Autodesk Fusion 360 part; units mm, degrees
(part 2 of 6)
sketch "Skizze3" plane through (0, 0, 0) normal (0, 1, 0) x (1, 0, 0)
  spline S0 degree 5 poles (100, -0.079) (99.9701, -0.0818) (99.9078, -0.0877) (99.8067, -0.0976) (99.657, -0.1128) (99.4452, -0.1351) (99.2102, -0.1605) (98.9548, -0.1887) (98.6833, -0.2193) (98.4004, -0.2518) (98.111, -0.2858) (97.8191, -0.3207) (97.527, -0.3562) (97.2355, -0.3922) (96.9443, -0.4285) (96.6525, -0.4653) (96.359, -0.5023) (96.0633, -0.5398) (95.7651, -0.5776) (95.4651, -0.6157) (95.1639, -0.6542) (94.8622, -0.6928) (94.5608, -0.7315) (94.2597, -0.7704) (93.9591, -0.8094) (93.6589, -0.8484) (93.3586, -0.8874) (93.058, -0.9265) (92.7571, -0.9656) (92.4557, -1.0047) (92.1541, -1.0439) (91.8523, -1.0832) (91.5504, -1.1226) (91.2487, -1.162) (90.9472, -1.2014) (90.6458, -1.2409) (90.3445, -1.2803) (90.0433, -1.3196) (89.742, -1.3589) (89.4406, -1.3981) (89.1392, -1.4371) (88.8377, -1.4761) (88.5362, -1.5151) (88.2347, -1.554) (87.9332, -1.5928) (87.6317, -1.6317) (87.3304, -1.6706) (87.029, -1.7094) (86.7278, -1.7483) (86.4266, -1.7871) (86.1253, -1.8258) (85.8242, -1.8645) (85.523, -1.903) (85.2218, -1.9413) (84.9206, -1.9795) (84.6194, -2.0175) (84.3181, -2.0554) (84.0169, -2.0932) (83.7156, -2.1308) (83.4143, -2.1685) (83.1131, -2.2061) (82.8119, -2.2437) (82.5107, -2.2812) (82.2095, -2.3187) (81.9084, -2.356) (81.6073, -2.3931) (81.3063, -2.4301) (81.0053, -2.467) (80.7043, -2.5037) (80.4032, -2.5403) (80.1022, -2.5768) (79.8011, -2.6132) (79.5, -2.6496) (79.1988, -2.6858) (78.8976, -2.722) (78.5964, -2.758) (78.2953, -2.7938) (77.9941, -2.8294) (77.693, -2.8648) (77.3919, -2.9) (77.0908, -2.9351) (76.7897, -2.97) (76.4886, -3.0048) (76.1875, -3.0395) (75.8863, -3.0741) (75.5852, -3.1086) (75.284, -3.1429) (74.9827, -3.1772) (74.6815, -3.2112) (74.3803, -3.2452) (74.0791, -3.2789) (73.7779, -3.3126) (73.4767, -3.3461) (73.1757, -3.3794) (72.8746, -3.4126) (72.5736, -3.4455) (72.2726, -3.4783) (71.9715, -3.5109) (71.6704, -3.5433) (71.3692, -3.5754) (71.068, -3.6073) (70.7668, -3.639) (70.4655, -3.6706) (70.1643, -3.702) (69.863, -3.7332) (69.5618, -3.7642) (69.2605, -3.7951) (68.9593, -3.8259) (68.658, -3.8565) (68.3567, -3.887) (68.0554, -3.9173) (67.754, -3.9474) (67.4527, -3.9773) (67.1514, -4.007) (66.8502, -4.0365) (66.5489, -4.0657) (66.2477, -4.0948) (65.9464, -4.1237) (65.6452, -4.1523) (65.3439, -4.1809) (65.0425, -4.2092) (64.7412, -4.2374) (64.4397, -4.2653) (64.1383, -4.293) (63.8369, -4.3203) (63.5354, -4.3474) (63.234, -4.3742) (62.9325, -4.4008) (62.6311, -4.4272) (62.3296, -4.4535) (62.0281, -4.4797) (61.7266, -4.5058) (61.425, -4.5319) (61.1234, -4.5578) (60.8218, -4.5835) (60.5202, -4.6089) (60.2185, -4.634) (59.9169, -4.6587) (59.6152, -4.6831) (59.3136, -4.7073) (59.0119, -4.7312) (58.7103, -4.755) (58.4086, -4.7786) (58.1069, -4.8022) (57.8052, -4.8256) (57.5035, -4.8489) (57.2018, -4.872) (56.9002, -4.8949) (56.5985, -4.9176) (56.2968, -4.9401) (55.995, -4.9622) (55.6933, -4.9841) (55.3915, -5.0057) (55.0897, -5.0271) (54.7878, -5.0482) (54.4859, -5.0692) (54.184, -5.0899) (53.8821, -5.1106) (53.5802, -5.1311) (53.2783, -5.1515) (52.9765, -5.1717) (52.6746, -5.1917) (52.3727, -5.2115) (52.0708, -5.2309) (51.7688, -5.25) (51.4669, -5.2688) (51.165, -5.2873) (50.863, -5.3055) (50.561, -5.3236) (50.2591, -5.3415) (49.9571, -5.3592) (49.6551, -5.3768) (49.3531, -5.3942) (49.0511, -5.4114) (48.7492, -5.4283) (48.4473, -5.4451) (48.1454, -5.4617) (47.8435, -5.478) (47.5416, -5.4941) (47.2397, -5.51) (46.9377, -5.5257) (46.6358, -5.5411) (46.3339, -5.5563) (46.0319, -5.5712) (45.7299, -5.5858) (45.428, -5.6001) (45.126, -5.6141) (44.824, -5.6279) (44.522, -5.6414) (44.22, -5.6547) (43.918, -5.6677) (43.6161, -5.6805) (43.3142, -5.6931) (43.0123, -5.7055) (42.7104, -5.7176) (42.4085, -5.7295) (42.1066, -5.7411) (41.8047, -5.7524) (41.5029, -5.7635) (41.2011, -5.7742) (40.8992, -5.7846) (40.5974, -5.7946) (40.2955, -5.8044) (39.9937, -5.8138) (39.6919, -5.823) (39.3902, -5.8319) (39.0885, -5.8405) (38.7868, -5.8489) (38.4851, -5.8571) (38.1835, -5.865) (37.8819, -5.8725) (37.5803, -5.8797) (37.2788, -5.8866) (36.9772, -5.8931) (36.6757, -5.8992) (36.3741, -5.905) (36.0726, -5.9104) (35.7711, -5.9156) (35.4695, -5.9204) (35.168, -5.925) (34.8666, -5.9293) (34.5651, -5.9333) (34.2637, -5.937) (33.9623, -5.9404) (33.661, -5.9434) (33.3597, -5.946) (33.0584, -5.9483) (32.7572, -5.9501) (32.456, -5.9515) (32.1548, -5.9524) (31.8537, -5.9529) (31.5526, -5.9531) (31.2515, -5.9528) (30.9504, -5.9522) (30.6494, -5.9512) (30.3485, -5.9499) (30.0475, -5.9482) (29.7466, -5.9461) (29.4458, -5.9436) (29.145, -5.9407) (28.8442, -5.9373) (28.5435, -5.9336) (28.2429, -5.9294) (27.9424, -5.9248) (27.6419, -5.9197) (27.3415, -5.9143) (27.0412, -5.9084) (26.741, -5.902) (26.4408, -5.8951) (26.1407, -5.8877) (25.8407, -5.8797) (25.5407, -5.8711) (25.2407, -5.8621) (24.9408, -5.8525) (24.641, -5.8425) (24.3412, -5.832) (24.0416, -5.8211) (23.742, -5.8097) (23.4425, -5.7978) (23.1431, -5.7854) (22.8438, -5.7724) (22.5447, -5.7588) (22.2456, -5.7445) (21.9467, -5.7296) (21.648, -5.7141) (21.3493, -5.6979) (21.0508, -5.6811) (20.7525, -5.6637) (20.4543, -5.6456) (20.1562, -5.627) (19.8583, -5.6077) (19.5606, -5.5877) (19.263, -5.5672) (18.9656, -5.5459) (18.6684, -5.5239) (18.3713, -5.5011) (18.0744, -5.4776) (17.7777, -5.4533) (17.4812, -5.4281) (17.1849, -5.4022) (16.8888, -5.3754) (16.5929, -5.3479) (16.2973, -5.3196) (16.002, -5.2905) (15.707, -5.2606) (15.4122, -5.2298) (15.1177, -5.198) (14.8235, -5.1652) (14.5295, -5.1315) (14.2358, -5.0967) (13.9425, -5.0609) (13.6494, -5.0241) (13.3568, -4.9863) (13.0645, -4.9475) (12.7726, -4.9076) (12.4812, -4.8668) (12.1903, -4.8248) (11.8998, -4.7817) (11.6099, -4.7374) (11.3205, -4.6919) (11.0316, -4.6451) (10.7433, -4.597) (10.4555, -4.5475) (10.1683, -4.4967) (9.8818, -4.4445) (9.5959, -4.3909) (9.3107, -4.3358) (9.0263, -4.2794) (8.7426, -4.2214) (8.4599, -4.1619) (8.1781, -4.1008) (7.8973, -4.038) (7.6176, -3.9735) (7.3391, -3.9071) (7.0618, -3.839) (6.786, -3.7689) (6.5116, -3.6969) (6.2388, -3.623) (5.9678, -3.5472) (5.6986, -3.4695) (5.4315, -3.3897) (5.1666, -3.3078) (4.9042, -3.2237) (4.6446, -3.1373) (4.3879, -3.0486) (4.1346, -2.9576) (3.885, -2.8644) (3.6396, -2.769) (3.3988, -2.6717) (3.1631, -2.5726) (2.9332, -2.4717) (2.7096, -2.3694) (2.493, -2.2657) (2.2839, -2.161) (2.083, -2.0552) (1.8907, -1.9488) (1.7074, -1.8419) (1.5334, -1.735) (1.369, -1.6286) (1.2143, -1.5232) (1.0693, -1.4191) (0.934, -1.316) (0.8082, -1.2129) (0.6918, -1.1092) (0.5844, -1.0058) (0.4855, -0.9051) (0.3947, -0.8087) (0.3123, -0.7125) (0.2388, -0.6096) (0.1745, -0.5023) (0.1187, -0.4087) (0.0713, -0.3317) (0.0338, -0.2303) (0.0087, -0.0853) (-0.0021, -0.004) (-0.0007, -0.0204) (0.0044, 0.0795) (0.0265, 0.2057) (0.072, 0.289) (0.1329, 0.3635) (0.2038, 0.4498) (0.2851, 0.5349) (0.3772, 0.6098) (0.4783, 0.6797) (0.587, 0.7508) (0.7036, 0.8233) (0.829, 0.8947) (0.9638, 0.9637) (1.108, 1.031) (1.2616, 1.0977) (1.4247, 1.1643) (1.5975, 1.2308) (1.7805, 1.2969) (1.9736, 1.3623) (2.1766, 1.4267) (2.3892, 1.4899) (2.6108, 1.5518) (2.8408, 1.6123) (3.0785, 1.6712) (3.3234, 1.7284) (3.5747, 1.7837) (3.8317, 1.8372) (4.0938, 1.8889) (4.3604, 1.9386) (4.6308, 1.9864) (4.9046, 2.0324) (5.1812, 2.0766) (5.4603, 2.119) (5.7416, 2.1597) (6.0247, 2.1989) (6.3095, 2.2364) (6.5958, 2.2725) (6.8833, 2.3072) (7.1719, 2.3406) (7.4616, 2.3727) (7.7521, 2.4037) (8.0434, 2.4334) (8.3354, 2.462) (8.628, 2.4895) (8.9213, 2.5159) (9.2152, 2.5411) (9.5096, 2.5653) (9.8044, 2.5884) (10.0998, 2.6106) (10.3955, 2.6319) (10.6917, 2.6524) (10.9882, 2.6722) (11.285, 2.6913) (11.5821, 2.7097) (11.8795, 2.7274) (12.1771, 2.7445) (12.475, 2.7608) (12.7732, 2.7763) (13.0716, 2.7912) (13.3702, 2.8053) (13.669, 2.8188) (13.968, 2.8316) (14.2672, 2.8438) (14.5665, 2.8554) (14.866, 2.8665) (15.1656, 2.8771) (15.4653, 2.8873) (15.7652, 2.8971) (16.0651, 2.9065) (16.3652, 2.9154) (16.6655, 2.9239) (16.9658, 2.9318) (17.2663, 2.9393) (17.567, 2.9462) (17.8678, 2.9525) (18.1687, 2.9585) (18.4697, 2.964) (18.7707, 2.9692) (19.0719, 2.974) (19.3731, 2.9786) (19.6743, 2.9829) (19.9756, 2.9869) (20.277, 2.9905) (20.5784, 2.9937) (20.8799, 2.9966) (21.1814, 2.9991) (21.4831, 3.0012) (21.7849, 3.0031) (22.0867, 3.0047) (22.3886, 3.0061) (22.6906, 3.0073) (22.9927, 3.0082) (23.2948, 3.0088) (23.5969, 3.0091) (23.8989, 3.009) (24.201, 3.0086) (24.5031, 3.0078) (24.8052, 3.0068) (25.1074, 3.0055) (25.4096, 3.0041) (25.7119, 3.0026) (26.0143, 3.0009) (26.3167, 2.999) (26.6192, 2.9968) (26.9216, 2.9944) (27.2241, 2.9916) (27.5265, 2.9885) (27.829, 2.9851) (28.1314, 2.9815) (28.434, 2.9777) (28.7366, 2.9737) (29.0393, 2.9696) (29.342, 2.9655) (29.6448, 2.9611) (29.9476, 2.9566) (30.2504, 2.9518) (30.5532, 2.9468) (30.856, 2.9416) (31.1587, 2.9361) (31.4614, 2.9305) (31.7642, 2.9247) (32.067, 2.9188) (32.3699, 2.9129) (32.6728, 2.9068) (32.9758, 2.9006) (33.2788, 2.8942) (33.5817, 2.8876) (33.8847, 2.8808) (34.1876, 2.8737) (34.4905, 2.8664) (34.7934, 2.8589) (35.0963, 2.8513) (35.3993, 2.8435) (35.7023, 2.8356) (36.0054, 2.8276) (36.3085, 2.8195) (36.6117, 2.8114) (36.9148, 2.803) (37.218, 2.7946) (37.5211, 2.786) (37.8242, 2.7772) (38.1273, 2.7683) (38.4303, 2.7592) (38.7334, 2.75) (39.0364, 2.7406) (39.3394, 2.7312) (39.6425, 2.7216) (39.9456, 2.7119) (40.2488, 2.7021) (40.552, 2.6922) (40.8552, 2.6823) (41.1585, 2.6722) (41.4618, 2.662) (41.7651, 2.6518) (42.0683, 2.6413) (42.3716, 2.6308) (42.6748, 2.6201) (42.9781, 2.6092) (43.2813, 2.5981) (43.5845, 2.5869) (43.8878, 2.5756) (44.191, 2.5641) (44.4943, 2.5525) (44.7975, 2.5409) (45.1007, 2.5291) (45.4039, 2.5174) (45.7071, 2.5055) (46.0103, 2.4937) (46.3135, 2.4817) (46.6168, 2.4697) (46.92, 2.4576) (47.2234, 2.4453) (47.5268, 2.433) (47.8302, 2.4205) (48.1336, 2.4079) (48.4371, 2.3952) (48.7405, 2.3824) (49.0439, 2.3695) (49.3473, 2.3565) (49.6507, 2.3435) (49.954, 2.3303) (50.2574, 2.3171) (50.5607, 2.3038) (50.8641, 2.2904) (51.1675, 2.277) (51.4709, 2.2636) (51.7743, 2.2501) (52.0777, 2.2366) (52.3812, 2.223) (52.6847, 2.2093) (52.9881, 2.1955) (53.2916, 2.1816) (53.5951, 2.1675) (53.8985, 2.1533) (54.2019, 2.139) (54.5054, 2.1246) (54.8088, 2.1102) (55.1123, 2.0959) (55.4158, 2.0815) (55.7193, 2.0672) (56.0229, 2.0528) (56.3264, 2.0383) (56.63, 2.0237) (56.9336, 2.0089) (57.2371, 1.9939) (57.5406, 1.9789) (57.8441, 1.9637) (58.1477, 1.9486) (58.4512, 1.9336) (58.7547, 1.9186) (59.0582, 1.9037) (59.3617, 1.8887) (59.6652, 1.8737) (59.9688, 1.8586) (60.2723, 1.8433) (60.5759, 1.8278) (60.8795, 1.8122) (61.1831, 1.7965) (61.4867, 1.7809) (61.7904, 1.7652) (62.0941, 1.7496) (62.3978, 1.7341) (62.7015, 1.7186) (63.0052, 1.7031) (63.3089, 1.6875) (63.6126, 1.6717) (63.9163, 1.6559) (64.22, 1.6399) (64.5237, 1.6239) (64.8273, 1.6079) (65.131, 1.5919) (65.4347, 1.5759) (65.7384, 1.56) (66.0421, 1.5441) (66.3458, 1.5282) (66.6495, 1.5122) (66.9532, 1.4963) (67.2568, 1.4802) (67.5605, 1.4641) (67.8641, 1.448) (68.1678, 1.4318) (68.4716, 1.4155) (68.7754, 1.3993) (69.0793, 1.383) (69.3832, 1.3667) (69.6871, 1.3504) (69.991, 1.3341) (70.2949, 1.3178) (70.5987, 1.3015) (70.9026, 1.2852) (71.2065, 1.2689) (71.5103, 1.2526) (71.8141, 1.2363) (72.118, 1.22) (72.4218, 1.2038) (72.7257, 1.1875) (73.0296, 1.1712) (73.3335, 1.1549) (73.6374, 1.1385) (73.9413, 1.1222) (74.2451, 1.1059) (74.549, 1.0896) (74.8528, 1.0733) (75.1566, 1.0571) (75.4604, 1.041) (75.7642, 1.0249) (76.068, 1.0088) (76.3717, 0.9927) (76.6755, 0.9766) (76.9793, 0.9605) (77.2831, 0.9444) (77.5869, 0.9282) (77.8907, 0.9121) (78.1944, 0.896) (78.4981, 0.88) (78.8018, 0.8639) (79.1054, 0.848) (79.4089, 0.8321) (79.7125, 0.8162) (80.0161, 0.8003) (80.3196, 0.7845) (80.6232, 0.7687) (80.9268, 0.7529) (81.2304, 0.7371) (81.5341, 0.7215) (81.8377, 0.7059) (82.1413, 0.6903) (82.4448, 0.6749) (82.7484, 0.6595) (83.0518, 0.6442) (83.3552, 0.629) (83.6585, 0.6139) (83.9618, 0.5988) (84.265, 0.5837) (84.5682, 0.5687) (84.8714, 0.5538) (85.1746, 0.5389) (85.4778, 0.5241) (85.781, 0.5093) (86.0842, 0.4947) (86.3873, 0.4801) (86.6904, 0.4657) (86.9935, 0.4514) (87.2965, 0.4372) (87.5995, 0.4233) (87.9025, 0.4095) (88.2054, 0.3959) (88.5083, 0.3825) (88.8112, 0.3692) (89.114, 0.3561) (89.4167, 0.3432) (89.7193, 0.3304) (90.0218, 0.3176) (90.3242, 0.305) (90.6266, 0.2925) (90.929, 0.2801) (91.2315, 0.268) (91.5341, 0.256) (91.8367, 0.2443) (92.1392, 0.2329) (92.4415, 0.2217) (92.7434, 0.2109) (93.0449, 0.2003) (93.3459, 0.19) (93.6466, 0.18) (93.9473, 0.1703) (94.2481, 0.161) (94.5494, 0.152) (94.8511, 0.1433) (95.1529, 0.135) (95.4543, 0.1271) (95.7544, 0.1196) (96.0526, 0.1124) (96.3484, 0.1058) (96.6419, 0.0996) (96.9336, 0.0939) (97.2249, 0.0888) (97.5167, 0.0844) (97.8092, 0.0806) (98.1019, 0.0775) (98.3924, 0.0752) (98.6765, 0.0736) (98.9495, 0.0728) (99.2063, 0.0727) (99.4426, 0.0732) (99.6555, 0.0744) (99.806, 0.0759) (99.9074, 0.0773) (99.97, 0.0784) (100, 0.079) knots 0 0 0 0 0 0 0.00142857 0.00285714 0.00428571 0.00571429 0.00714286 0.00857143 0.01 0.01142857 0.01285714 0.01428571 0.01571429 0.01714286 0.01857143 0.02 0.02142857 0.02285714 0.02428571 0.02571429 0.02714286 0.02857143 0.03 0.03142857 0.03285714 0.03428571 0.03571429 0.03714286 0.03857143 0.04 0.04142857 0.04285714 0.04428571 0.04571429 0.04714286 0.04857143 0.05 0.05142857 0.05285714 0.05428571 0.05571429 0.05714286 0.05857143 0.06 0.06142857 0.06285714 0.06428571 0.06571429 0.06714286 0.06857143 0.07 0.07142857 0.07285714 0.07428571 0.07571429 0.07714286 0.07857143 0.08 0.08142857 0.08285714 0.08428571 0.08571429 0.08714286 0.08857143 0.09 0.09142857 0.09285714 0.09428571 0.09571429 0.09714286 0.09857143 0.1 0.10142857 0.10285714 0.10428571 0.10571429 0.10714286 0.10857143 0.11 0.11142857 0.11285714 0.11428571 0.11571429 0.11714286 0.11857143 0.12 0.12142857 0.12285714 0.12428571 0.12571429 0.12714286 0.12857143 0.13 0.13142857 0.13285714 0.13428571 0.13571429 0.13714286 0.13857143 0.14 0.14142857 0.14285714 0.14428571 0.14571429 0.14714286 0.14857143 0.15 0.15142857 0.15285714 0.15428571 0.15571429 0.15714286 0.15857143 0.16 0.16142857 0.16285714 0.16428571 0.16571429 0.16714286 0.16857143 0.17 0.17142857 0.17285714 0.17428571 0.17571429 0.17714286 0.17857143 0.18 0.18142857 0.18285714 0.18428571 0.18571429 0.18714286 0.18857143 0.19 0.19142857 0.19285714 0.19428571 0.19571429 0.19714286 0.19857143 0.2 0.20142857 0.20285714 0.20428571 0.20571429 0.20714286 0.20857143 0.21 0.21142857 0.21285714 0.21428571 0.21571429 0.21714286 0.21857143 0.22 0.22142857 0.22285714 0.22428571 0.22571429 0.22714286 0.22857143 0.23 0.23142857 0.23285714 0.23428571 0.23571429 0.23714286 0.23857143 0.24 0.24142857 0.24285714 0.24428571 0.24571429 0.24714286 0.24857143 0.25 0.25142857 0.25285714 0.25428571 0.25571429 0.25714286 0.25857143 0.26 0.26142857 0.26285714 0.26428571 0.26571429 0.26714286 0.26857143 0.27 0.27142857 0.27285714 0.27428571 0.27571429 0.27714286 0.27857143 0.28 0.28142857 0.28285714 0.28428571 0.28571429 0.28714286 0.28857143 0.29 0.29142857 0.29285714 0.29428571 0.29571429 0.29714286 0.29857143 0.3 0.30142857 0.30285714 0.30428571 0.30571429 0.30714286 0.30857143 0.31 0.31142857 0.31285714 0.31428571 0.31571429 0.31714286 0.31857143 0.32 0.32142857 0.32285714 0.32428571 0.32571429 0.32714286 0.32857143 0.33 0.33142857 0.33285714 0.33428571 0.33571429 0.33714286 0.33857143 0.34 0.34142857 0.34285714 0.34428571 0.34571429 0.34714286 0.34857143 0.35 0.35142857 0.35285714 0.35428571 0.35571429 0.35714286 0.35857143 0.36 0.36142857 0.36285714 0.36428571 0.36571429 0.36714286 0.36857143 0.37 0.37142857 0.37285714 0.37428571 0.37571429 0.37714286 0.37857143 0.38 0.38142857 0.38285714 0.38428571 0.38571429 0.38714286 0.38857143 0.39 0.39142857 0.39285714 0.39428571 0.39571429 0.39714286 0.39857143 0.4 0.40142857 0.40285714 0.40428571 0.40571429 0.40714286 0.40857143 0.41 0.41142857 0.41285714 0.41428571 0.41571429 0.41714286 0.41857143 0.42 0.42142857 0.42285714 0.42428571 0.42571429 0.42714286 0.42857143 0.43 0.43142857 0.43285714 0.43428571 0.43571429 0.43714286 0.43857143 0.44 0.44142857 0.44285714 0.44428571 0.44571429 0.44714286 0.44857143 0.45 0.45142857 0.45285714 0.45428571 0.45571429 0.45714286 0.45857143 0.46 0.46142857 0.46285714 0.46428571 0.46571429 0.46714286 0.46857143 0.47 0.47142857 0.47285714 0.47428571 0.47571429 0.47714286 0.47857143 0.48 0.48142857 0.48285714 0.48428571 0.48571429 0.48714286 0.48857143 0.49 0.49142857 0.49285714 0.49428571 0.49571429 0.49714286 0.49857143 0.5 0.50142857 0.50285714 0.50428571 0.50571429 0.50714286 0.50857143 0.51 0.51142857 0.51285714 0.51428571 0.51571429 0.51714286 0.51857143 0.52 0.52142857 0.52285714 0.52428571 0.52571429 0.52714286 0.52857143 0.53 0.53142857 0.53285714 0.53428571 0.53571429 0.53714286 0.53857143 0.54 0.54142857 0.54285714 0.54428571 0.54571429 0.54714286 0.54857143 0.55 0.55142857 0.55285714 0.55428571 0.55571429 0.55714286 0.55857143 0.56 0.56142857 0.56285714 0.56428571 0.56571429 0.56714286 0.56857143 0.57 0.57142857 0.57285714 0.57428571 0.57571429 0.57714286 0.57857143 0.58 0.58142857 0.58285714 0.58428571 0.58571429 0.58714286 0.58857143 0.59 0.59142857 0.59285714 0.59428571 0.59571429 0.59714286 0.59857143 0.6 0.60142857 0.60285714 0.60428571 0.60571429 0.60714286 0.60857143 0.61 0.61142857 0.61285714 0.61428571 0.61571429 0.61714286 0.61857143 0.62 0.62142857 0.62285714 0.62428571 0.62571429 0.62714286 0.62857143 0.63 0.63142857 0.63285714 0.63428571 0.63571429 0.63714286 0.63857143 0.64 0.64142857 0.64285714 0.64428571 0.64571429 0.64714286 0.64857143 0.65 0.65142857 0.65285714 0.65428571 0.65571429 0.65714286 0.65857143 0.66 0.66142857 0.66285714 0.66428571 0.66571429 0.66714286 0.66857143 0.67 0.67142857 0.67285714 0.67428571 0.67571429 0.67714286 0.67857143 0.68 0.68142857 0.68285714 0.68428571 0.68571429 0.68714286 0.68857143 0.69 0.69142857 0.69285714 0.69428571 0.69571429 0.69714286 0.69857143 0.7 0.70142857 0.70285714 0.70428571 0.70571429 0.70714286 0.70857143 0.71 0.71142857 0.71285714 0.71428571 0.71571429 0.71714286 0.71857143 0.72 0.72142857 0.72285714 0.72428571 0.72571429 0.72714286 0.72857143 0.73 0.73142857 0.73285714 0.73428571 0.73571429 0.73714286 0.73857143 0.74 0.74142857 0.74285714 0.74428571 0.74571429 0.74714286 0.74857143 0.75 0.75142857 0.75285714 0.75428571 0.75571429 0.75714286 0.75857143 0.76 0.76142857 0.76285714 0.76428571 0.76571429 0.76714286 0.76857143 0.77 0.77142857 0.77285714 0.77428571 0.77571429 0.77714286 0.77857143 0.78 0.78142857 0.78285714 0.78428571 0.78571429 0.78714286 0.78857143 0.79 0.79142857 0.79285714 0.79428571 0.79571429 0.79714286 0.79857143 0.8 0.80142857 0.80285714 0.80428571 0.80571429 0.80714286 0.80857143 0.81 0.81142857 0.81285714 0.81428571 0.81571429 0.81714286 0.81857143 0.82 0.82142857 0.82285714 0.82428571 0.82571429 0.82714286 0.82857143 0.83 0.83142857 0.83285714 0.83428571 0.83571429 0.83714286 0.83857143 0.84 0.84142857 0.84285714 0.84428571 0.84571429 0.84714286 0.84857143 0.85 0.85142857 0.85285714 0.85428571 0.85571429 0.85714286 0.85857143 0.86 0.86142857 0.86285714 0.86428571 0.86571429 0.86714286 0.86857143 0.87 0.87142857 0.87285714 0.87428571 0.87571429 0.87714286 0.87857143 0.88 0.88142857 0.88285714 0.88428571 0.88571429 0.88714286 0.88857143 0.89 0.89142857 0.89285714 0.89428571 0.89571429 0.89714286 0.89857143 0.9 0.90142857 0.90285714 0.90428571 0.90571429 0.90714286 0.90857143 0.91 0.91142857 0.91285714 0.91428571 0.91571429 0.91714286 0.91857143 0.92 0.92142857 0.92285714 0.92428571 0.92571429 0.92714286 0.92857143 0.93 0.93142857 0.93285714 0.93428571 0.93571429 0.93714286 0.93857143 0.94 0.94142857 0.94285714 0.94428571 0.94571429 0.94714286 0.94857143 0.95 0.95142857 0.95285714 0.95428571 0.95571429 0.95714286 0.95857143 0.96 0.96142857 0.96285714 0.96428571 0.96571429 0.96714286 0.96857143 0.97 0.97142857 0.97285714 0.97428571 0.97571429 0.97714286 0.97857143 0.98 0.98142857 0.98285714 0.98428571 0.98571429 0.98714286 0.98857143 0.99 0.99142857 0.99285714 0.99428571 0.99571429 0.99714286 0.99857143 1 1 1 1 1 1
  line L0 (100, 0.079) -> (100, -0.079)
  point P0 (99.317, -0.149)
  point P1 (97.976, -0.302)
  point P2 (96.433, -0.493)
  point P3 (94.814, -0.699)
  point P4 (93.177, -0.911)
  point P5 (91.532, -1.125)
  point P6 (89.887, -1.34)
  point P7 (88.242, -1.553)
  point P8 (86.598, -1.765)
  point P9 (84.956, -1.975)
  point P10 (83.314, -2.181)
  point P11 (81.673, -2.385)
  point P12 (80.034, -2.585)
  point P13 (78.394, -2.782)
  point P14 (76.755, -2.974)
  point P15 (75.116, -3.162)
  point P16 (73.477, -3.346)
  point P17 (71.84, -3.525)
  point P18 (70.202, -3.698)
  point P19 (68.564, -3.866)
  point P20 (66.926, -4.029)
  point P21 (65.289, -4.186)
  point P22 (63.651, -4.337)
  point P23 (62.013, -4.481)
  point P24 (60.374, -4.621)
  point P25 (58.735, -4.753)
  point P26 (57.096, -4.88)
  point P27 (55.457, -5.001)
  point P28 (53.817, -5.115)
  point P29 (52.177, -5.224)
  point P30 (50.537, -5.325)
  point P31 (48.897, -5.42)
  point P32 (47.258, -5.509)
  point P33 (45.619, -5.591)
  point P34 (43.98, -5.665)
  point P35 (42.342, -5.732)
  point P36 (40.705, -5.791)
  point P37 (39.069, -5.841)
  point P38 (37.435, -5.883)
  point P39 (35.802, -5.915)
  point P40 (34.17, -5.938)
  point P41 (32.54, -5.951)
  point P42 (30.912, -5.952)
  point P43 (29.286, -5.942)
  point P44 (27.663, -5.92)
  point P45 (26.044, -5.885)
  point P46 (24.428, -5.835)
  point P47 (22.816, -5.771)
  point P48 (21.21, -5.69)
  point P49 (19.611, -5.591)
  point P50 (18.02, -5.473)
  point P51 (16.438, -5.333)
  point P52 (14.868, -5.17)
  point P53 (13.311, -4.98)
  point P54 (11.772, -4.762)
  point P55 (10.256, -4.512)
  point P56 (8.767, -4.226)
  point P57 (7.316, -3.901)
  point P58 (5.92, -3.533)
  point P59 (4.605, -3.123)
  point P60 (3.414, -2.677)
  point P61 (2.411, -2.224)
  point P62 (1.642, -1.801)
  point P63 (1.093, -1.435)
  point P64 (0.71, -1.124)
  point P65 (0.44, -0.856)
  point P66 (0.248, -0.619)
  point P67 (0.117, -0.406)
  point P68 (0.034, -0.209)
  point P69 (0.001, -0.027)
  point P70 (0.02, 0.151)
  point P71 (0.106, 0.329)
  point P72 (0.255, 0.501)
  point P73 (0.467, 0.671)
  point P74 (0.752, 0.85)
  point P75 (1.142, 1.045)
  point P76 (1.688, 1.263)
  point P77 (2.463, 1.51)
  point P78 (3.51, 1.769)
  point P79 (4.791, 2.013)
  point P80 (6.217, 2.224)
  point P81 (7.72, 2.4)
  point P82 (9.265, 2.545)
  point P83 (10.837, 2.662)
  point P84 (12.427, 2.758)
  point P85 (14.03, 2.834)
  point P86 (15.642, 2.893)
  point P87 (17.261, 2.939)
  point P88 (18.887, 2.971)
  point P89 (20.517, 2.993)
  point P90 (22.151, 3.005)
  point P91 (23.789, 3.009)
  point P92 (25.428, 3.004)
  point P93 (27.07, 2.993)
  point P94 (28.713, 2.974)
  point P95 (30.359, 2.95)
  point P96 (32.005, 2.92)
  point P97 (33.653, 2.886)
  point P98 (35.301, 2.846)
  point P99 (36.951, 2.802)
  point P100 (38.601, 2.754)
  point P101 (40.251, 2.702)
  point P102 (41.903, 2.647)
  point P103 (43.555, 2.588)
  point P104 (45.207, 2.525)
  point P105 (46.859, 2.46)
  point P106 (48.513, 2.392)
  point P107 (50.167, 2.321)
  point P108 (51.821, 2.248)
  point P109 (53.476, 2.173)
  point P110 (55.131, 2.095)
  point P111 (56.787, 2.016)
  point P112 (58.443, 1.934)
  point P113 (60.099, 1.852)
  point P114 (61.756, 1.767)
  point P115 (63.414, 1.682)
  point P116 (65.072, 1.595)
  point P117 (66.73, 1.508)
  point P118 (68.388, 1.42)
  point P119 (70.048, 1.331)
  point P120 (71.708, 1.242)
  point P121 (73.368, 1.153)
  point P122 (75.028, 1.064)
  point P123 (76.687, 0.976)
  point P124 (78.346, 0.888)
  point P125 (80.003, 0.801)
  point P126 (81.66, 0.715)
  point P127 (83.316, 0.631)
  point P128 (84.969, 0.549)
  point P129 (86.621, 0.469)
  point P130 (88.271, 0.393)
  point P131 (89.918, 0.322)
  point P132 (91.562, 0.255)
  point P133 (93.201, 0.195)
  point P134 (94.829, 0.144)
  point P135 (96.436, 0.104)
  point P136 (97.97, 0.079)
  point P137 (99.314, 0.073)
surface "Profilschnitt_L2" add patch profiles "Skizze3" section 1 separate body makes body 3
scale "Profiltiefe_L2" factor 1.8 about (0, 0, 0) bodies 3
move_body "Station_L2" bodies 3 to x (1, 0, 0) y (0, 1, 0) z (0, 0, 1) at (0, -669.9071, 10.646)
sketch "Skizze4" plane through (0, 0, 0) normal (0, 1, 0) x (1, 0, 0)
  spline S0 degree 5 poles (100, -0.15) (99.9698, -0.1532) (99.9069, -0.1598) (99.8054, -0.1706) (99.6556, -0.1869) (99.4448, -0.2102) (99.2115, -0.2365) (98.9585, -0.2653) (98.6894, -0.2962) (98.4089, -0.3287) (98.1211, -0.3622) (97.8299, -0.3962) (97.5376, -0.4305) (97.2451, -0.4648) (96.9524, -0.4991) (96.6588, -0.5333) (96.3636, -0.5675) (96.0663, -0.6017) (95.7669, -0.6359) (95.4657, -0.6701) (95.1634, -0.7042) (94.8605, -0.7382) (94.5577, -0.7721) (94.2552, -0.8059) (93.9531, -0.8396) (93.6512, -0.8731) (93.3495, -0.9065) (93.0476, -0.9398) (92.7455, -0.973) (92.4431, -1.0061) (92.1403, -1.0391) (91.8374, -1.072) (91.5343, -1.1047) (91.2312, -1.1374) (90.9281, -1.1699) (90.625, -1.2023) (90.322, -1.2347) (90.019, -1.267) (89.7161, -1.2992) (89.4132, -1.3314) (89.1102, -1.3636) (88.8072, -1.3956) (88.5041, -1.4276) (88.2009, -1.4595) (87.8975, -1.4912) (87.5941, -1.5229) (87.2907, -1.5544) (86.9871, -1.5858) (86.6836, -1.6171) (86.3801, -1.6483) (86.0766, -1.6795) (85.7732, -1.7106) (85.4697, -1.7417) (85.1663, -1.7727) (84.8628, -1.8038) (84.5593, -1.8349) (84.2557, -1.8659) (83.9521, -1.8968) (83.6485, -1.9277) (83.3449, -1.9586) (83.0413, -1.9893) (82.7378, -2.02) (82.4342, -2.0506) (82.1306, -2.0811) (81.827, -2.1116) (81.5234, -2.142) (81.2197, -2.1725) (80.9161, -2.2029) (80.6124, -2.2334) (80.3086, -2.2637) (80.0049, -2.294) (79.7012, -2.3242) (79.3975, -2.3544) (79.0939, -2.3844) (78.7902, -2.4144) (78.4864, -2.4443) (78.1827, -2.4742) (77.8789, -2.5041) (77.5751, -2.5339) (77.2713, -2.5637) (76.9674, -2.5935) (76.6636, -2.6233) (76.3598, -2.6531) (76.0561, -2.6829) (75.7523, -2.7126) (75.4486, -2.7423) (75.1449, -2.7719) (74.8412, -2.8013) (74.5375, -2.8308) (74.2337, -2.8601) (73.93, -2.8894) (73.6262, -2.9186) (73.3225, -2.9478) (73.0187, -2.977) (72.7151, -3.0062) (72.4114, -3.0354) (72.1077, -3.0646) (71.8041, -3.0937) (71.5005, -3.1226) (71.1968, -3.1514) (70.8931, -3.1801) (70.5894, -3.2087) (70.2857, -3.2372) (69.982, -3.2656) (69.6783, -3.294) (69.3747, -3.3223) (69.071, -3.3505) (68.7674, -3.3787) (68.4638, -3.4069) (68.1603, -3.435) (67.8567, -3.463) (67.5532, -3.491) (67.2497, -3.5189) (66.9462, -3.5467) (66.6426, -3.5745) (66.3391, -3.6021) (66.0355, -3.6297) (65.7319, -3.6571) (65.4284, -3.6845) (65.1248, -3.7116) (64.8213, -3.7386) (64.5177, -3.7655) (64.2142, -3.7922) (63.9107, -3.8188) (63.6073, -3.8453) (63.3038, -3.8717) (63.0003, -3.8982) (62.6968, -3.9245) (62.3932, -3.9509) (62.0897, -3.9771) (61.7862, -4.0033) (61.4827, -4.0293) (61.1792, -4.0552) (60.8757, -4.0809) (60.5722, -4.1065) (60.2688, -4.1319) (59.9654, -4.1571) (59.662, -4.1823) (59.3586, -4.2073) (59.0552, -4.2323) (58.7519, -4.257) (58.4485, -4.2817) (58.1451, -4.3062) (57.8416, -4.3305) (57.5382, -4.3547) (57.2348, -4.3788) (56.9313, -4.4028) (56.6279, -4.4267) (56.3246, -4.4505) (56.0212, -4.4742) (55.7178, -4.4977) (55.4145, -4.5211) (55.1112, -4.5442) (54.8078, -4.5671) (54.5044, -4.5897) (54.201, -4.6121) (53.8976, -4.6343) (53.5942, -4.6565) (53.2908, -4.6785) (52.9874, -4.7005) (52.6841, -4.7225) (52.3808, -4.7443) (52.0775, -4.7661) (51.7742, -4.7877) (51.4709, -4.809) (51.1676, -4.83) (50.8643, -4.8508) (50.561, -4.8712) (50.2577, -4.8915) (49.9545, -4.9115) (49.6512, -4.9314) (49.348, -4.9511) (49.0448, -4.9707) (48.7416, -4.9902) (48.4384, -5.0096) (48.1352, -5.0289) (47.832, -5.048) (47.5287, -5.067) (47.2255, -5.0857) (46.9222, -5.1042) (46.619, -5.1224) (46.3158, -5.1403) (46.0126, -5.1578) (45.7095, -5.1752) (45.4065, -5.1922) (45.1034, -5.2091) (44.8004, -5.2257) (44.4974, -5.2422) (44.1943, -5.2585) (43.8913, -5.2747) (43.5883, -5.2906) (43.2852, -5.3063) (42.9822, -5.3218) (42.6791, -5.3371) (42.376, -5.352) (42.0729, -5.3668) (41.7699, -5.3812) (41.4668, -5.3954) (41.1639, -5.4093) (40.8609, -5.423) (40.558, -5.4364) (40.2551, -5.4495) (39.9523, -5.4623) (39.6494, -5.4749) (39.3467, -5.4871) (39.0439, -5.4992) (38.7411, -5.511) (38.4384, -5.5225) (38.1357, -5.5338) (37.833, -5.5448) (37.5303, -5.5556) (37.2276, -5.566) (36.9249, -5.5762) (36.6223, -5.586) (36.3195, -5.5955) (36.0169, -5.6046) (35.7142, -5.6134) (35.4116, -5.6218) (35.109, -5.6299) (34.8065, -5.6376) (34.5041, -5.645) (34.2017, -5.6521) (33.8993, -5.6588) (33.597, -5.6653) (33.2947, -5.6714) (32.9923, -5.6771) (32.69, -5.6826) (32.3877, -5.6877) (32.0854, -5.6924) (31.7831, -5.6968) (31.4809, -5.7008) (31.1788, -5.7044) (30.8767, -5.7077) (30.5747, -5.7105) (30.2727, -5.713) (29.9708, -5.7151) (29.6689, -5.7167) (29.367, -5.718) (29.0651, -5.7188) (28.7633, -5.7192) (28.4615, -5.7192) (28.1597, -5.7188) (27.858, -5.718) (27.5564, -5.7168) (27.2548, -5.7152) (26.9533, -5.7132) (26.652, -5.7108) (26.3507, -5.708) (26.0495, -5.7047) (25.7484, -5.701) (25.4474, -5.6967) (25.1464, -5.6918) (24.8455, -5.6863) (24.5447, -5.6803) (24.2439, -5.6737) (23.9432, -5.6666) (23.6427, -5.659) (23.3422, -5.6509) (23.0419, -5.6424) (22.7418, -5.6333) (22.4418, -5.6237) (22.1419, -5.6136) (21.8422, -5.6028) (21.5426, -5.5913) (21.2432, -5.5792) (20.9438, -5.5665) (20.6446, -5.5531) (20.3455, -5.5391) (20.0466, -5.5244) (19.7477, -5.5091) (19.4491, -5.4931) (19.1507, -5.4765) (18.8524, -5.4591) (18.5545, -5.4409) (18.2568, -5.422) (17.9594, -5.4023) (17.6622, -5.3817) (17.3652, -5.3603) (17.0684, -5.3381) (16.7718, -5.315) (16.4753, -5.2911) (16.1791, -5.2663) (15.8831, -5.2407) (15.5874, -5.2142) (15.2919, -5.1867) (14.9968, -5.1584) (14.702, -5.1291) (14.4076, -5.0988) (14.1136, -5.0674) (13.8201, -5.0351) (13.5269, -5.0016) (13.2341, -4.9671) (12.9417, -4.9315) (12.6498, -4.8948) (12.3582, -4.857) (12.0671, -4.818) (11.7764, -4.7779) (11.4862, -4.7365) (11.1965, -4.6938) (10.9075, -4.6497) (10.6192, -4.6043) (10.3315, -4.5575) (10.0447, -4.5093) (9.7585, -4.4596) (9.4732, -4.4085) (9.1887, -4.356) (8.9051, -4.302) (8.6225, -4.2465) (8.3408, -4.1894) (8.0602, -4.1305) (7.7808, -4.0699) (7.5027, -4.0075) (7.226, -3.9431) (6.9507, -3.8769) (6.677, -3.8087) (6.4051, -3.7385) (6.135, -3.6664) (5.8669, -3.5922) (5.6011, -3.5159) (5.3377, -3.4374) (5.0769, -3.3567) (4.819, -3.2736) (4.5643, -3.1883) (4.3131, -3.1008) (4.0657, -3.011) (3.8225, -2.9191) (3.5839, -2.8252) (3.3505, -2.7292) (3.1226, -2.6313) (2.9008, -2.5315) (2.6856, -2.4301) (2.4774, -2.3275) (2.2767, -2.2241) (2.0839, -2.1203) (1.8992, -2.0164) (1.7229, -1.9124) (1.5554, -1.8083) (1.3968, -1.7039) (1.2471, -1.5995) (1.1063, -1.4957) (0.9742, -1.3933) (0.8506, -1.2926) (0.7354, -1.1923) (0.6286, -1.0909) (0.53, -0.9884) (0.4394, -0.888) (0.3563, -0.7927) (0.281, -0.6986) (0.2138, -0.5963) (0.1548, -0.487) (0.1038, -0.3939) (0.0606, -0.3221) (0.0271, -0.2204) (0.0055, -0.0625) (-0.0028, 0.0091) (-0.0003, -0.0252) (0.0079, 0.0969) (0.0316, 0.2301) (0.0746, 0.3075) (0.1323, 0.3792) (0.2013, 0.4693) (0.2805, 0.5567) (0.3689, 0.6311) (0.4651, 0.7007) (0.5684, 0.7731) (0.6792, 0.8469) (0.798, 0.9188) (0.925, 0.9876) (1.0603, 1.0544) (1.2038, 1.1205) (1.3558, 1.1861) (1.5166, 1.2512) (1.6866, 1.3155) (1.8657, 1.3788) (2.0541, 1.441) (2.2515, 1.5019) (2.4577, 1.5615) (2.6724, 1.6197) (2.8953, 1.6763) (3.1259, 1.7312) (3.3638, 1.7844) (3.6084, 1.8358) (3.8593, 1.8852) (4.116, 1.9326) (4.3778, 1.978) (4.6442, 2.0215) (4.9147, 2.0631) (5.1886, 2.1031) (5.4656, 2.1415) (5.7452, 2.1784) (6.0271, 2.2138) (6.311, 2.2478) (6.5966, 2.2804) (6.8839, 2.3115) (7.1726, 2.3413) (7.4625, 2.3698) (7.7535, 2.3969) (8.0455, 2.4229) (8.3383, 2.4477) (8.6319, 2.4715) (8.926, 2.4943) (9.2208, 2.5161) (9.516, 2.5371) (9.8118, 2.5573) (10.1081, 2.5766) (10.4048, 2.5951) (10.702, 2.6128) (10.9995, 2.6297) (11.2974, 2.6459) (11.5957, 2.6612) (11.8942, 2.6758) (12.1931, 2.6897) (12.4922, 2.7029) (12.7915, 2.7155) (13.0911, 2.7274) (13.3908, 2.7387) (13.6908, 2.7495) (13.991, 2.7597) (14.2914, 2.7694) (14.592, 2.7786) (14.8927, 2.7873) (15.1936, 2.7956) (15.4947, 2.8034) (15.7959, 2.8107) (16.0972, 2.8176) (16.3986, 2.8241) (16.7001, 2.8301) (17.0017, 2.8357) (17.3034, 2.8408) (17.6052, 2.8455) (17.9071, 2.8497) (18.2091, 2.8535) (18.5113, 2.8569) (18.8135, 2.8599) (19.1159, 2.8626) (19.4183, 2.8649) (19.7208, 2.867) (20.0233, 2.8687) (20.3259, 2.8702) (20.6285, 2.8714) (20.9313, 2.8723) (21.2341, 2.8729) (21.537, 2.8732) (21.8401, 2.8731) (22.1432, 2.8727) (22.4464, 2.872) (22.7496, 2.8711) (23.0529, 2.87) (23.3562, 2.8687) (23.6595, 2.8672) (23.9628, 2.8655) (24.2662, 2.8635) (24.5695, 2.8612) (24.873, 2.8586) (25.1764, 2.8557) (25.4799, 2.8526) (25.7834, 2.8491) (26.087, 2.8455) (26.3906, 2.8417) (26.6942, 2.8377) (26.9979, 2.8335) (27.3016, 2.8292) (27.6053, 2.8247) (27.909, 2.8199) (28.2128, 2.815) (28.5166, 2.8098) (28.8204, 2.8044) (29.1243, 2.7989) (29.4282, 2.7931) (29.7322, 2.7872) (30.0362, 2.7811) (30.3402, 2.7749) (30.6443, 2.7685) (30.9483, 2.762) (31.2524, 2.7553) (31.5565, 2.7485) (31.8605, 2.7415) (32.1646, 2.7343) (32.4688, 2.727) (32.7729, 2.7194) (33.0771, 2.7116) (33.3814, 2.7037) (33.6857, 2.6956) (33.99, 2.6873) (34.2943, 2.679) (34.5986, 2.6706) (34.9029, 2.6621) (35.2072, 2.6536) (35.5115, 2.6449) (35.8158, 2.6362) (36.1201, 2.6272) (36.4244, 2.6181) (36.7287, 2.6088) (37.033, 2.5992) (37.3374, 2.5896) (37.6418, 2.5797) (37.9462, 2.5698) (38.2506, 2.5597) (38.555, 2.5497) (38.8595, 2.5395) (39.1639, 2.5293) (39.4684, 2.519) (39.7729, 2.5086) (40.0774, 2.4981) (40.382, 2.4874) (40.6865, 2.4767) (40.9911, 2.4658) (41.2956, 2.4548) (41.6001, 2.4437) (41.9046, 2.4325) (42.2091, 2.4213) (42.5136, 2.4099) (42.8182, 2.3985) (43.1227, 2.3871) (43.4273, 2.3756) (43.7319, 2.3641) (44.0365, 2.3525) (44.3412, 2.3407) (44.6458, 2.3289) (44.9504, 2.3169) (45.255, 2.3047) (45.5596, 2.2923) (45.8641, 2.2798) (46.1687, 2.2673) (46.4734, 2.2546) (46.778, 2.2419) (47.0827, 2.2291) (47.3874, 2.2163) (47.6921, 2.2036) (47.9968, 2.1909) (48.3015, 2.1781) (48.6061, 2.1654) (48.9108, 2.1526) (49.2155, 2.1396) (49.5202, 2.1265) (49.8248, 2.1133) (50.1295, 2.0999) (50.4341, 2.0863) (50.7388, 2.0725) (51.0434, 2.0588) (51.3481, 2.0449) (51.6528, 2.0311) (51.9575, 2.0173) (52.2622, 2.0035) (52.567, 1.9897) (52.8718, 1.9759) (53.1766, 1.962) (53.4814, 1.948) (53.7863, 1.9339) (54.0912, 1.9197) (54.396, 1.9054) (54.7008, 1.891) (55.0055, 1.8766) (55.3102, 1.862) (55.6149, 1.8475) (55.9196, 1.8329) (56.2244, 1.8183) (56.5292, 1.8037) (56.834, 1.789) (57.139, 1.7744) (57.4439, 1.7597) (57.7489, 1.7449) (58.0538, 1.7301) (58.3586, 1.7151) (58.6635, 1.7001) (58.9683, 1.685) (59.273, 1.6699) (59.5778, 1.6547) (59.8826, 1.6395) (60.1875, 1.6242) (60.4923, 1.609) (60.7972, 1.5937) (61.1022, 1.5784) (61.4071, 1.5631) (61.7121, 1.5478) (62.017, 1.5324) (62.322, 1.5169) (62.627, 1.5014) (62.932, 1.4859) (63.237, 1.4704) (63.5421, 1.4549) (63.8472, 1.4393) (64.1522, 1.4237) (64.4573, 1.408) (64.7624, 1.3923) (65.0675, 1.3765) (65.3726, 1.3607) (65.6776, 1.3449) (65.9827, 1.3291) (66.2877, 1.3133) (66.5928, 1.2974) (66.8979, 1.2816) (67.203, 1.2658) (67.5081, 1.2501) (67.8131, 1.2342) (68.1182, 1.2184) (68.4232, 1.2026) (68.7282, 1.1867) (69.0331, 1.1709) (69.3381, 1.1551) (69.643, 1.1393) (69.948, 1.1236) (70.253, 1.1079) (70.558, 1.0923) (70.863, 1.0767) (71.168, 1.0611) (71.4729, 1.0454) (71.7779, 1.0298) (72.0828, 1.0141) (72.3876, 0.9984) (72.6925, 0.9828) (72.9974, 0.9672) (73.3023, 0.9516) (73.6072, 0.9362) (73.9121, 0.9209) (74.217, 0.9056) (74.5219, 0.8904) (74.8268, 0.8753) (75.1316, 0.8602) (75.4364, 0.8452) (75.7411, 0.8301) (76.0458, 0.815) (76.3504, 0.7999) (76.6551, 0.7847) (76.9597, 0.7696) (77.2643, 0.7545) (77.569, 0.7396) (77.8736, 0.7247) (78.1782, 0.7101) (78.4828, 0.6956) (78.7874, 0.6812) (79.092, 0.667) (79.3966, 0.6529) (79.7011, 0.6389) (80.0055, 0.6249) (80.31, 0.6109) (80.6144, 0.5969) (80.9188, 0.583) (81.2231, 0.5692) (81.5274, 0.5556) (81.8317, 0.5421) (82.136, 0.5288) (82.4402, 0.5157) (82.7444, 0.5027) (83.0486, 0.4897) (83.3527, 0.4769) (83.6567, 0.4641) (83.9608, 0.4514) (84.2648, 0.4388) (84.5688, 0.4263) (84.8728, 0.414) (85.1769, 0.4018) (85.4809, 0.3898) (85.7849, 0.378) (86.0889, 0.3665) (86.3928, 0.3551) (86.6966, 0.344) (87.0004, 0.3332) (87.3041, 0.3225) (87.6078, 0.3119) (87.9114, 0.3015) (88.2151, 0.2912) (88.5187, 0.281) (88.8224, 0.271) (89.126, 0.2612) (89.4295, 0.2516) (89.7329, 0.2423) (90.0362, 0.2333) (90.3395, 0.2246) (90.6426, 0.2162) (90.9458, 0.2081) (91.2489, 0.2001) (91.5521, 0.1924) (91.8553, 0.1848) (92.1584, 0.1775) (92.4612, 0.1704) (92.7638, 0.1635) (93.0659, 0.1571) (93.3677, 0.151) (93.6691, 0.1453) (93.9705, 0.1401) (94.2719, 0.1353) (94.5735, 0.1308) (94.8753, 0.1267) (95.1771, 0.123) (95.4782, 0.1197) (95.7781, 0.1167) (96.0762, 0.1143) (96.3721, 0.1124) (96.6657, 0.111) (96.9575, 0.1103) (97.2484, 0.1103) (97.5392, 0.1111) (97.83, 0.1126) (98.12, 0.1148) (98.407, 0.1178) (98.6872, 0.1213) (98.9562, 0.1253) (99.2095, 0.1298) (99.4431, 0.1345) (99.6545, 0.1395) (99.8047, 0.1436) (99.9066, 0.1468) (99.9697, 0.1489) (100, 0.15) knots 0 0 0 0 0 0 0.00142857 0.00285714 0.00428571 0.00571429 0.00714286 0.00857143 0.01 0.01142857 0.01285714 0.01428571 0.01571429 0.01714286 0.01857143 0.02 0.02142857 0.02285714 0.02428571 0.02571429 0.02714286 0.02857143 0.03 0.03142857 0.03285714 0.03428571 0.03571429 0.03714286 0.03857143 0.04 0.04142857 0.04285714 0.04428571 0.04571429 0.04714286 0.04857143 0.05 0.05142857 0.05285714 0.05428571 0.05571429 0.05714286 0.05857143 0.06 0.06142857 0.06285714 0.06428571 0.06571429 0.06714286 0.06857143 0.07 0.07142857 0.07285714 0.07428571 0.07571429 0.07714286 0.07857143 0.08 0.08142857 0.08285714 0.08428571 0.08571429 0.08714286 0.08857143 0.09 0.09142857 0.09285714 0.09428571 0.09571429 0.09714286 0.09857143 0.1 0.10142857 0.10285714 0.10428571 0.10571429 0.10714286 0.10857143 0.11 0.11142857 0.11285714 0.11428571 0.11571429 0.11714286 0.11857143 0.12 0.12142857 0.12285714 0.12428571 0.12571429 0.12714286 0.12857143 0.13 0.13142857 0.13285714 0.13428571 0.13571429 0.13714286 0.13857143 0.14 0.14142857 0.14285714 0.14428571 0.14571429 0.14714286 0.14857143 0.15 0.15142857 0.15285714 0.15428571 0.15571429 0.15714286 0.15857143 0.16 0.16142857 0.16285714 0.16428571 0.16571429 0.16714286 0.16857143 0.17 0.17142857 0.17285714 0.17428571 0.17571429 0.17714286 0.17857143 0.18 0.18142857 0.18285714 0.18428571 0.18571429 0.18714286 0.18857143 0.19 0.19142857 0.19285714 0.19428571 0.19571429 0.19714286 0.19857143 0.2 0.20142857 0.20285714 0.20428571 0.20571429 0.20714286 0.20857143 0.21 0.21142857 0.21285714 0.21428571 0.21571429 0.21714286 0.21857143 0.22 0.22142857 0.22285714 0.22428571 0.22571429 0.22714286 0.22857143 0.23 0.23142857 0.23285714 0.23428571 0.23571429 0.23714286 0.23857143 0.24 0.24142857 0.24285714 0.24428571 0.24571429 0.24714286 0.24857143 0.25 0.25142857 0.25285714 0.25428571 0.25571429 0.25714286 0.25857143 0.26 0.26142857 0.26285714 0.26428571 0.26571429 0.26714286 0.26857143 0.27 0.27142857 0.27285714 0.27428571 0.27571429 0.27714286 0.27857143 0.28 0.28142857 0.28285714 0.28428571 0.28571429 0.28714286 0.28857143 0.29 0.29142857 0.29285714 0.29428571 0.29571429 0.29714286 0.29857143 0.3 0.30142857 0.30285714 0.30428571 0.30571429 0.30714286 0.30857143 0.31 0.31142857 0.31285714 0.31428571 0.31571429 0.31714286 0.31857143 0.32 0.32142857 0.32285714 0.32428571 0.32571429 0.32714286 0.32857143 0.33 0.33142857 0.33285714 0.33428571 0.33571429 0.33714286 0.33857143 0.34 0.34142857 0.34285714 0.34428571 0.34571429 0.34714286 0.34857143 0.35 0.35142857 0.35285714 0.35428571 0.35571429 0.35714286 0.35857143 0.36 0.36142857 0.36285714 0.36428571 0.36571429 0.36714286 0.36857143 0.37 0.37142857 0.37285714 0.37428571 0.37571429 0.37714286 0.37857143 0.38 0.38142857 0.38285714 0.38428571 0.38571429 0.38714286 0.38857143 0.39 0.39142857 0.39285714 0.39428571 0.39571429 0.39714286 0.39857143 0.4 0.40142857 0.40285714 0.40428571 0.40571429 0.40714286 0.40857143 0.41 0.41142857 0.41285714 0.41428571 0.41571429 0.41714286 0.41857143 0.42 0.42142857 0.42285714 0.42428571 0.42571429 0.42714286 0.42857143 0.43 0.43142857 0.43285714 0.43428571 0.43571429 0.43714286 0.43857143 0.44 0.44142857 0.44285714 0.44428571 0.44571429 0.44714286 0.44857143 0.45 0.45142857 0.45285714 0.45428571 0.45571429 0.45714286 0.45857143 0.46 0.46142857 0.46285714 0.46428571 0.46571429 0.46714286 0.46857143 0.47 0.47142857 0.47285714 0.47428571 0.47571429 0.47714286 0.47857143 0.48 0.48142857 0.48285714 0.48428571 0.48571429 0.48714286 0.48857143 0.49 0.49142857 0.49285714 0.49428571 0.49571429 0.49714286 0.49857143 0.5 0.50142857 0.50285714 0.50428571 0.50571429 0.50714286 0.50857143 0.51 0.51142857 0.51285714 0.51428571 0.51571429 0.51714286 0.51857143 0.52 0.52142857 0.52285714 0.52428571 0.52571429 0.52714286 0.52857143 0.53 0.53142857 0.53285714 0.53428571 0.53571429 0.53714286 0.53857143 0.54 0.54142857 0.54285714 0.54428571 0.54571429 0.54714286 0.54857143 0.55 0.55142857 0.55285714 0.55428571 0.55571429 0.55714286 0.55857143 0.56 0.56142857 0.56285714 0.56428571 0.56571429 0.56714286 0.56857143 0.57 0.57142857 0.57285714 0.57428571 0.57571429 0.57714286 0.57857143 0.58 0.58142857 0.58285714 0.58428571 0.58571429 0.58714286 0.58857143 0.59 0.59142857 0.59285714 0.59428571 0.59571429 0.59714286 0.59857143 0.6 0.60142857 0.60285714 0.60428571 0.60571429 0.60714286 0.60857143 0.61 0.61142857 0.61285714 0.61428571 0.61571429 0.61714286 0.61857143 0.62 0.62142857 0.62285714 0.62428571 0.62571429 0.62714286 0.62857143 0.63 0.63142857 0.63285714 0.63428571 0.63571429 0.63714286 0.63857143 0.64 0.64142857 0.64285714 0.64428571 0.64571429 0.64714286 0.64857143 0.65 0.65142857 0.65285714 0.65428571 0.65571429 0.65714286 0.65857143 0.66 0.66142857 0.66285714 0.66428571 0.66571429 0.66714286 0.66857143 0.67 0.67142857 0.67285714 0.67428571 0.67571429 0.67714286 0.67857143 0.68 0.68142857 0.68285714 0.68428571 0.68571429 0.68714286 0.68857143 0.69 0.69142857 0.69285714 0.69428571 0.69571429 0.69714286 0.69857143 0.7 0.70142857 0.70285714 0.70428571 0.70571429 0.70714286 0.70857143 0.71 0.71142857 0.71285714 0.71428571 0.71571429 0.71714286 0.71857143 0.72 0.72142857 0.72285714 0.72428571 0.72571429 0.72714286 0.72857143 0.73 0.73142857 0.73285714 0.73428571 0.73571429 0.73714286 0.73857143 0.74 0.74142857 0.74285714 0.74428571 0.74571429 0.74714286 0.74857143 0.75 0.75142857 0.75285714 0.75428571 0.75571429 0.75714286 0.75857143 0.76 0.76142857 0.76285714 0.76428571 0.76571429 0.76714286 0.76857143 0.77 0.77142857 0.77285714 0.77428571 0.77571429 0.77714286 0.77857143 0.78 0.78142857 0.78285714 0.78428571 0.78571429 0.78714286 0.78857143 0.79 0.79142857 0.79285714 0.79428571 0.79571429 0.79714286 0.79857143 0.8 0.80142857 0.80285714 0.80428571 0.80571429 0.80714286 0.80857143 0.81 0.81142857 0.81285714 0.81428571 0.81571429 0.81714286 0.81857143 0.82 0.82142857 0.82285714 0.82428571 0.82571429 0.82714286 0.82857143 0.83 0.83142857 0.83285714 0.83428571 0.83571429 0.83714286 0.83857143 0.84 0.84142857 0.84285714 0.84428571 0.84571429 0.84714286 0.84857143 0.85 0.85142857 0.85285714 0.85428571 0.85571429 0.85714286 0.85857143 0.86 0.86142857 0.86285714 0.86428571 0.86571429 0.86714286 0.86857143 0.87 0.87142857 0.87285714 0.87428571 0.87571429 0.87714286 0.87857143 0.88 0.88142857 0.88285714 0.88428571 0.88571429 0.88714286 0.88857143 0.89 0.89142857 0.89285714 0.89428571 0.89571429 0.89714286 0.89857143 0.9 0.90142857 0.90285714 0.90428571 0.90571429 0.90714286 0.90857143 0.91 0.91142857 0.91285714 0.91428571 0.91571429 0.91714286 0.91857143 0.92 0.92142857 0.92285714 0.92428571 0.92571429 0.92714286 0.92857143 0.93 0.93142857 0.93285714 0.93428571 0.93571429 0.93714286 0.93857143 0.94 0.94142857 0.94285714 0.94428571 0.94571429 0.94714286 0.94857143 0.95 0.95142857 0.95285714 0.95428571 0.95571429 0.95714286 0.95857143 0.96 0.96142857 0.96285714 0.96428571 0.96571429 0.96714286 0.96857143 0.97 0.97142857 0.97285714 0.97428571 0.97571429 0.97714286 0.97857143 0.98 0.98142857 0.98285714 0.98428571 0.98571429 0.98714286 0.98857143 0.99 0.99142857 0.99285714 0.99428571 0.99571429 0.99714286 0.99857143 1 1 1 1 1 1
  line L0 (100, 0.15) -> (100, -0.15)
  point P0 (99.314, -0.225)
  point P1 (97.986, -0.378)
  point P2 (96.428, -0.56)
  point P3 (94.791, -0.746)
  point P4 (93.136, -0.93)
  point P5 (91.476, -1.111)
  point P6 (89.812, -1.289)
  point P7 (88.148, -1.465)
  point P8 (86.48, -1.638)
  point P9 (84.812, -1.809)
  point P10 (83.143, -1.979)
  point P11 (81.474, -2.147)
  point P12 (79.804, -2.314)
  point P13 (78.134, -2.479)
  point P14 (76.463, -2.643)
  point P15 (74.793, -2.806)
  point P16 (73.123, -2.967)
  point P17 (71.454, -3.127)
  point P18 (69.785, -3.284)
  point P19 (68.117, -3.439)
  point P20 (66.45, -3.592)
  point P21 (64.783, -3.742)
  point P22 (63.117, -3.888)
  point P23 (61.451, -4.032)
  point P24 (59.786, -4.172)
  point P25 (58.122, -4.308)
  point P26 (56.458, -4.44)
  point P27 (54.795, -4.568)
  point P28 (53.132, -4.69)
  point P29 (51.47, -4.809)
  point P30 (49.809, -4.921)
  point P31 (48.149, -5.028)
  point P32 (46.489, -5.13)
  point P33 (44.831, -5.224)
  point P34 (43.174, -5.312)
  point P35 (41.517, -5.393)
  point P36 (39.862, -5.466)
  point P37 (38.209, -5.531)
  point P38 (36.557, -5.588)
  point P39 (34.906, -5.635)
  point P40 (33.258, -5.672)
  point P41 (31.611, -5.699)
  point P42 (29.967, -5.715)
  point P43 (28.325, -5.719)
  point P44 (26.686, -5.711)
  point P45 (25.052, -5.69)
  point P46 (23.422, -5.653)
  point P47 (21.799, -5.601)
  point P48 (20.183, -5.531)
  point P49 (18.575, -5.442)
  point P50 (16.979, -5.331)
  point P51 (15.393, -5.196)
  point P52 (13.822, -5.035)
  point P53 (12.27, -4.845)
  point P54 (10.739, -4.623)
  point P55 (9.239, -4.365)
  point P56 (7.779, -4.069)
  point P57 (6.375, -3.73)
  point P58 (5.052, -3.348)
  point P59 (3.848, -2.928)
  point P60 (2.814, -2.49)
  point P61 (1.992, -2.068)
  point P62 (1.38, -1.691)
  point P63 (0.938, -1.363)
  point P64 (0.619, -1.079)
  point P65 (0.387, -0.827)
  point P66 (0.219, -0.6)
  point P67 (0.102, -0.392)
  point P68 (0.028, -0.198)
  point P69 (0, -0.016)
  point P70 (0.022, 0.161)
  point P71 (0.102, 0.34)
  point P72 (0.243, 0.513)
  point P73 (0.44, 0.682)
  point P74 (0.698, 0.857)
  point P75 (1.039, 1.043)
  point P76 (1.496, 1.242)
  point P77 (2.124, 1.462)
  point P78 (2.98, 1.696)
  point P79 (4.089, 1.927)
  point P80 (5.414, 2.134)
  point P81 (6.873, 2.31)
  point P82 (8.406, 2.453)
  point P83 (9.978, 2.568)
  point P84 (11.575, 2.66)
  point P85 (13.189, 2.731)
  point P86 (14.815, 2.785)
  point P87 (16.45, 2.825)
  point P88 (18.091, 2.852)
  point P89 (19.738, 2.867)
  point P90 (21.389, 2.873)
  point P91 (23.045, 2.87)
  point P92 (24.703, 2.86)
  point P93 (26.363, 2.842)
  point P94 (28.025, 2.818)
  point P95 (29.689, 2.788)
  point P96 (31.355, 2.753)
  point P97 (33.022, 2.713)
  point P98 (34.691, 2.668)
  point P99 (36.36, 2.62)
  point P100 (38.03, 2.567)
  point P101 (39.701, 2.511)
  point P102 (41.373, 2.452)
  point P103 (43.045, 2.39)
  point P104 (44.718, 2.326)
  point P105 (46.391, 2.258)
  point P106 (48.065, 2.188)
  point P107 (49.739, 2.117)
  point P108 (51.413, 2.042)
  point P109 (53.088, 1.966)
  point P110 (54.764, 1.888)
  point P111 (56.439, 1.808)
  point P112 (58.116, 1.727)
  point P113 (59.792, 1.644)
  point P114 (61.469, 1.56)
  point P115 (63.147, 1.475)
  point P116 (64.826, 1.389)
  point P117 (66.505, 1.302)
  point P118 (68.184, 1.215)
  point P119 (69.862, 1.128)
  point P120 (71.54, 1.042)
  point P121 (73.217, 0.956)
  point P122 (74.894, 0.872)
  point P123 (76.569, 0.789)
  point P124 (78.243, 0.707)
  point P125 (79.916, 0.629)
  point P126 (81.587, 0.553)
  point P127 (83.256, 0.481)
  point P128 (84.923, 0.412)
  point P129 (86.589, 0.348)
  point P130 (88.252, 0.29)
  point P131 (89.913, 0.237)
  point P132 (91.57, 0.192)
  point P133 (93.221, 0.154)
  point P134 (94.86, 0.127)
  point P135 (96.471, 0.112)
  point P136 (98.001, 0.114)
  point P137 (99.315, 0.132)
surface "Profilschnitt_L3" add patch profiles "Skizze4" section 1 separate body makes body 4
scale "Profiltiefe_L3" factor 1.05 about (0, 0, 0) bodies 4
move_body "Station_L3" bodies 4 to x (1, 0, 0) y (0, 1, 0) z (0, 0, 1) at (0, -1279.8142, 21.2919)